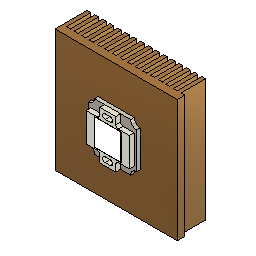
10W LED v7 (Autodesk Fusion 360 design; units mm, degrees)
Autodesk Fusion 360 part; units mm, degrees
sketch "COmponent" plane through (0, 0, 0) normal (0, 0, 1) x (1, 0, 0)
  line L0 (10, 10) -> (-10, 10)
  line L1 (-10, 10) -> (-10, -10)
  line L2 (-10, -10) -> (10, -10)
  line L3 (10, -10) -> (10, 10)
  line L4 (10, 10) -> (-10, -10) construction
  line L5 (-10, 10) -> (10, -10) construction
  line L6 (-9, 6) -> (-9, -6)
  line L7 (9, -6) -> (9, 6)
  line L8 (3.3, 2.2) -> (-9, -6) construction
  line L9 (-9, 6) -> (9, -6) construction
  line L10 (3.3, 10) -> (-3.3, 10)
  line L11 (-3.3, -10) -> (3.3, -10)
  line L12 (3.3, 10) -> (-3.3, -10) construction
  line L13 (-3.3, 10) -> (3.3, -10) construction
  line L14 (3.3, -10) -> (3.3, -6)
  line L15 (3.3, 6) -> (3.3, 10)
  line L16 (-9, -6) -> (-3.3, -6)
  line L17 (3.3, -6) -> (9, -6)
  line L18 (-3.3, 10) -> (-3.3, 6)
  line L19 (-3.3, -6) -> (-3.3, -10)
  line L20 (9, 6) -> (3.3, 6)
  line L21 (-3.3, 6) -> (-9, 6)
  line L22 (-3.3, -6) -> (3.3, -9.487) construction
  line L23 (3.3, -6) -> (-3.3, -9.487) construction
  line L24 (2.1, -6.7435) -> (-2.1, -6.7435)
  line L25 (-2.1, -6.7435) -> (-2.1, -8.7435)
  line L26 (-2.1, -8.7435) -> (2.1, -8.7435)
  line L27 (2.1, -8.7435) -> (2.1, -6.7435)
  line L28 (2.1, -6.7435) -> (-2.1, -8.7435) construction
  line L29 (-2.1, -6.7435) -> (2.1, -8.7435) construction
  line L30 (9, 0) -> (6.8583, 0)
  line L31 (2.1, 6.7435) -> (-2.1, 6.7435)
  line L32 (-2.1, 6.7435) -> (-2.1, 8.7435)
  line L33 (-2.1, 8.7435) -> (2.1, 8.7435)
  line L34 (2.1, 8.7435) -> (2.1, 6.7435)
  circle A0 centre (10, -10) radius 2.5
  circle A1 centre (10, 10) radius 2.5
  circle A2 centre (-10, 10) radius 2.5
  circle A3 centre (-10, -10) radius 2.5
  point P0 (0, -7.7435)
  dimension "d1" = 20
  dimension "d2" = 20
  dimension "d3" = 18
  dimension "d4" = 12
  dimension "d5" = 6.6
  dimension "d6" = 20
  dimension "d7" = 4.2
  dimension "d8" = 2
  dimension "d9" = 5
  dimension "d10" = 5
  dimension "d11" = 5
  dimension "d12" = 5
  constraint perpendicular L0 L1
  constraint parallel L0 L2
  constraint parallel L1 L3
  constraint horizontal L0
  constraint coincident L4 origin
  constraint coincident L5 origin
  constraint perpendicular L6 L20
  constraint parallel L16 L20
  constraint parallel L6 L7
  constraint horizontal L20
  constraint coincident L8 origin
  constraint coincident L9 origin
  constraint perpendicular L10 L18
  constraint parallel L10 L11
  constraint parallel L14 L18
  constraint horizontal L10
  constraint coincident L12 origin
  constraint coincident L13 origin
  constraint collinear L14 L15
  constraint coincident L14.end L16
  constraint collinear L16 L17
  constraint coincident L16.end L18
  constraint collinear L18 L19
  constraint coincident L18.end L20
  constraint collinear L20 L21
  constraint coincident L14 L22.end
  constraint coincident L19 L23.end
  constraint perpendicular L24 L25
  constraint parallel L24 L26
  constraint parallel L25 L27
  constraint horizontal L24
  constraint coincident L28 P0
  constraint coincident L29 P0
  constraint midpoint L23 P0
  constraint midpoint L7 L30.start
  constraint perpendicular L7 L30
  constraint symmetric L24.start L30 L31.start
  constraint symmetric L24.end L30 L31.end
  constraint symmetric L25.end L30 L32.end
  constraint symmetric L26.end L30 L33.end
  constraint coincident L2.end L3.start
  constraint coincident L0.start L3.end
  constraint coincident L0.end L1.start
  constraint coincident L1.end L2.start
  measures "d1" distance of L1.end L2.end
  measures "d2" distance of L0.end L1.end
  measures "d3" distance of L6.end L7.start
  measures "d4" distance of L6.start L6.end
  measures "d5" distance of L11.start L11.end
  measures "d6" distance of L10.end L11.start
  measures "d7" distance of L25.end L26.end
  measures "d8" distance of L24.end L25.end
  measures "d9" diameter of A0
  measures "d10" diameter of A1
  measures "d11" diameter of A2
  measures "d12" diameter of A3
extrude "Extrude1" add sketch "COmponent" against normal blind 1.5 contours L0 L2 L6 L7 L10 L11 L14 L15 L16 L17 L18 L19 L20 L21 | L0 L2 L3 L7 L14 L15 L17 L20 A0 A1 | L0 L1 L2 L6 L16 L18 L19 L21 A2 A3 | L24 L25 L26 L27 | L31 L32 L33 L34 makes body 1
extrude "Extrude2" add sketch "COmponent" along normal blind 2 separate body contours L0 L2 L6 L7 L10 L11 L14 L15 L16 L17 L18 L19 L20 L21 makes body 2
sketch "LED" plane through (0, 0, 2) normal (0, 0, 1) x (1, 0, 0)
  line L0 (2.1, -6.7435) -> (2.1, -8.7435)
  line L1 (2.1, -8.7435) -> (-2.1, -8.7435)
  line L2 (-2.1, -8.7435) -> (-2.1, -6.7435)
  line L3 (-2.1, -6.7435) -> (2.1, -6.7435)
  line L4 (-2.1, 8.7435) -> (2.1, 8.7435)
  line L5 (2.1, 8.7435) -> (2.1, 6.7435)
  line L6 (2.1, 6.7435) -> (-2.1, 6.7435)
  line L7 (-2.1, 6.7435) -> (-2.1, 8.7435)
  line L8 (-3.3, 6) -> (-9, 6)
  line L9 (-9, 6) -> (-9, -6)
  line L10 (-9, -6) -> (-3.3, -6)
  line L11 (-3.3, -6) -> (-3.3, -10)
  line L12 (-3.3, -10) -> (3.3, -10)
  line L13 (3.3, -10) -> (3.3, -6)
  line L14 (3.3, -6) -> (9, -6)
  line L15 (9, -6) -> (9, 6)
  line L16 (9, 6) -> (3.3, 6)
  line L17 (3.3, 6) -> (3.3, 10)
  line L18 (3.3, 10) -> (-3.3, 10)
  line L19 (-3.3, 10) -> (-3.3, 6)
  line L20 (5.5, 5.5) -> (-5.5, 5.5)
  line L21 (-5.5, 5.5) -> (-5.5, -5.5)
  line L22 (-5.5, -5.5) -> (5.5, -5.5)
  line L23 (5.5, -5.5) -> (5.5, 5.5)
  line L24 (5.5, 5.5) -> (-5.5, -5.5) construction
  line L25 (-5.5, 5.5) -> (5.5, -5.5) construction
  dimension "d17" = 11
  dimension "d18" = 11
  constraint perpendicular L20 L21
  constraint parallel L20 L22
  constraint parallel L21 L23
  constraint horizontal L20
  constraint coincident L24 origin
  constraint coincident L25 origin
  measures "d17" distance of L20.end L21.end
  measures "d18" distance of L21.end L22.end
extrude "Extrude3" cut sketch "LED" against normal blind 1 contours L20 L21 L22 L23 bodies 2
extrude "Extrude4" add 1 faces at (-1.8333, 1.8333, 1) along direction (0, 0, 1) blind 0.9 separate body on bodies 2 makes body 3
fillet "Fillet1" radius 1 12 edges at (-2.1, 8.7435, 1) (2.1, 8.7435, 1) (-2.1, 6.7435, 1) (2.1, 6.7435, 1) (3.3, 6, 1) (-3.3, 6, 1) (3.3, -6, 1) (-3.3, -6, 1) (-2.1, -6.7435, 1) (2.1, -6.7435, 1) (2.1, -8.7435, 1) (-2.1, -8.7435, 1) on bodies 2
ref_plane "WorkPlane1" through (0, 0, -1.5) normal (0, 0, -1) x (-1, 0, 0)
sketch "heatsink" plane through (0, 0, -1.5) normal (0, 0, -1) x (1, 0, 0)
  line L0 (-25.4, -25.4) -> (25.4, -25.4)
  line L1 (25.4, -25.4) -> (25.4, 25.4)
  line L2 (25.4, 25.4) -> (-25.4, 25.4)
  line L3 (-25.4, 25.4) -> (-25.4, -25.4)
  line L4 (-25.4, -25.4) -> (25.4, 25.4) construction
  line L5 (25.4, -25.4) -> (-25.4, 25.4) construction
  circle A0 centre (0, 0) radius 19.05
  dimension "d25" = 50.8
  dimension "d26" = 50.8
  dimension "d27" = 38.1
  constraint perpendicular L0 L1
  constraint parallel L0 L2
  constraint parallel L1 L3
  constraint horizontal L0
  constraint coincident L4 A0.centre
  constraint coincident L5 A0.centre
  constraint coincident A0.centre origin
  measures "d25" distance of L1.end L2.end
  measures "d26" distance of L0.end L1.end
  measures "d27" diameter of A0
extrude "Extrude5" add sketch "heatsink" along normal blind 3.175 separate body contours L0 L1 L2 L3 | A0 makes body 4
sketch "sink slots" plane through (0, 0, -4.675) normal (0, 0, -1) x (-1, 0, 0)
  line L0 (25.4, -25.4) -> (25.4, 25.4)
  line L1 (25.4, 25.4) -> (-25.4, 25.4)
  line L2 (-25.4, 25.4) -> (-25.4, -25.4)
  line L3 (-25.4, -25.4) -> (25.4, -25.4)
  line L4 (-25.4, 25.4) -> (-23.8125, 25.4)
  line L5 (-23.8125, 25.4) -> (-23.8125, -25.4)
  line L6 (-23.8125, -25.4) -> (-25.4, -25.4)
  line L7 (-25.4, -25.4) -> (-25.4, 25.4)
  line L8 (-22.225, 25.4) -> (-22.225, -25.4)
  line L9 (-20.6375, 25.4) -> (-20.6375, -25.4)
  line L10 (-19.05, 25.4) -> (-19.05, -25.4)
  line L11 (-17.4625, 25.4) -> (-17.4625, -25.4)
  line L12 (-15.875, 25.4) -> (-15.875, -25.4)
  line L13 (-14.2875, 25.4) -> (-14.2875, -25.4)
  line L14 (-12.7, 25.4) -> (-12.7, -25.4)
  line L15 (-11.1125, 25.4) -> (-11.1125, -25.4)
  line L16 (-9.525, 25.4) -> (-9.525, -25.4)
  line L17 (-7.9375, 25.4) -> (-7.9375, -25.4)
  line L18 (-6.35, 25.4) -> (-6.35, -25.4)
  line L19 (-4.7625, 25.4) -> (-4.7625, -25.4)
  line L20 (-3.175, 25.4) -> (-3.175, -25.4)
  line L21 (-1.5875, 25.4) -> (-1.5875, -25.4)
  line L22 (0, 25.4) -> (0, -25.4)
  line L23 (1.5875, 25.4) -> (1.5875, -25.4)
  line L24 (3.175, 25.4) -> (3.175, -25.4)
  line L25 (4.7625, 25.4) -> (4.7625, -25.4)
  line L26 (6.35, 25.4) -> (6.35, -25.4)
  line L27 (7.9375, 25.4) -> (7.9375, -25.4)
  line L28 (9.525, 25.4) -> (9.525, -25.4)
  line L29 (11.1125, 25.4) -> (11.1125, -25.4)
  line L30 (12.7, 25.4) -> (12.7, -25.4)
  line L31 (14.2875, 25.4) -> (14.2875, -25.4)
  line L32 (15.875, 25.4) -> (15.875, -25.4)
  line L33 (17.4625, 25.4) -> (17.4625, -25.4)
  line L34 (19.05, 25.4) -> (19.05, -25.4)
  line L35 (20.6375, 25.4) -> (20.6375, -25.4)
  line L36 (22.225, 25.4) -> (22.225, -25.4)
  line L37 (23.8125, 25.4) -> (23.8125, -25.4)
  dimension "d30" = 1.5875
  dimension "d33" = 1.5875
  dimension "d34" = 0
  constraint horizontal L4
  constraint vertical L5
  constraint horizontal L6
  constraint vertical L7
  constraint coincident L1.end L2.start
  measures "d30" distance of L1.end L4.end
extrude "Extrude6" add sketch "sink slots" along normal blind 10.16 contours L0 L1 L3 L37 | L1 L3 L35 L36 | L1 L3 L33 L34 | L1 L3 L31 L32 | L1 L3 L29 L30 | L1 L3 L27 L28 | L1 L3 L25 L26 | L1 L3 L23 L24 | L1 L3 L21 L22 | L1 L3 L19 L20 | L1 L3 L17 L18 | L1 L3 L15 L16 | L1 L3 L13 L14 | L1 L3 L11 L12 | L1 L3 L9 L10 | L1 L3 L5 L8 bodies 4
extrude "Extrude7" cut sketch "heatsink" along normal blind 20.32 from surface at 3.175 contours A0 bodies 4
named bodies: "metal", "Plastic", "LED", "Heatsink"
